Autodesk Fusion 360 part; units mm, degrees
(part 3 of 3)
sketch "草图3 (22)" plane through (286.45, 0, 0) normal (1, 0, 0) x (0, 0, -1) in component "16_CPU_VERTICAL_SIDE_FLUSH_TO_BEAM"
  line L0 (-16, 22) -> (-16, 38)
  line L1 (-16, 38) -> (-108, 237.84)
  line L2 (-108, 237.84) -> (-124, 237.84)
  line L3 (-124, 237.84) -> (-16, 22)
extrude "CPU side diagonal" add sketch "草图3 (22)" along normal blind 16 bodies 36 in component "16_CPU_VERTICAL_SIDE_FLUSH_TO_BEAM"
ref_plane "工作平面1" through (0, -6, 0) normal (0, 1, 0) x (0, 0, 1) in component "16_PCI_INSET_SIDE_16_45mm"
sketch "草图1 (33)" plane through (0, -6, 0) normal (0, 1, 0) x (1, 0, 0) in component "16_PCI_INSET_SIDE_16_45mm"
  line L0 (12.45, 0, 12) -> (28.45, 0, 12)
  line L1 (28.45, 0, 12) -> (12, -140, 12)
  line L2 (12, -140, 12) -> (-4, -140, 12)
  line L3 (-4, -140, 12) -> (12.45, 0, 12)
extrude "PCI taper 16.45 over 140 mm height" add sketch "草图1 (33)" along normal blind 247.84 separate body contours L0 L1 L2 L3 in plane through (0, 6, 0) normal (0, 1, 0) makes body 37 in component "16_PCI_INSET_SIDE_16_45mm"
ref_plane "工作平面2" through (0, 0, 16) normal (0, 0, 1) x (1, 0, 0) in component "16_PCI_INSET_SIDE_16_45mm"
sketch "草图2 (24)" plane through (0, 0, 16) normal (0, 0, 1) x (1, 0, 0) in component "16_PCI_INSET_SIDE_16_45mm"
  line L0 (-4.1, 22) -> (28.6, 22)
  line L1 (28.6, 22) -> (28.6, 237.84)
  line L2 (28.6, 237.84) -> (-4.1, 237.84)
  line L3 (-4.1, 237.84) -> (-4.1, 22)
extrude "PCI side open window" cut sketch "草图2 (24)" along normal blind 108 bodies 37 in component "16_PCI_INSET_SIDE_16_45mm"
ref_plane "工作平面3" through (-4, 0, 0) normal (1, 0, 0) x (0, 1, 0) in component "16_PCI_INSET_SIDE_16_45mm"
sketch "草图3 (23)" plane through (-4, 0, 0) normal (1, 0, 0) x (0, 0, -1) in component "16_PCI_INSET_SIDE_16_45mm"
  line L0 (-16, 22) -> (-16, 38)
  line L1 (-16, 38) -> (-108, 237.84)
  line L2 (-108, 237.84) -> (-124, 237.84)
  line L3 (-124, 237.84) -> (-16, 22)
extrude "PCI diagonal before taper trim" add sketch "草图3 (23)" along normal blind 32.45 bodies 37 in component "16_PCI_INSET_SIDE_16_45mm"
ref_plane "工作平面4" through (0, -5.9, 0) normal (0, 1, 0) x (0, 0, 1) in component "16_PCI_INSET_SIDE_16_45mm"
sketch "草图4 (21)" plane through (0, -5.9, 0) normal (0, 1, 0) x (1, 0, 0) in component "16_PCI_INSET_SIDE_16_45mm"
  line L0 (-10, 0, 11.8) -> (12.45, 0, 11.8)
  line L1 (12.45, 0, 11.8) -> (-4, -140, 11.8)
  line L2 (-4, -140, 11.8) -> (-10, -140, 11.8)
  line L3 (-10, -140, 11.8) -> (-10, 0, 11.8)
extrude "Trim diagonal outer tapered face" cut sketch "草图4 (21)" along normal blind 248.1 contours L0 L1 L2 L3 in plane through (0, 5.9, 0) normal (0, 1, 0) bodies 37 in component "16_PCI_INSET_SIDE_16_45mm"
ref_plane "工作平面5" through (0, -5.9, 0) normal (0, 1, 0) x (0, 0, 1) in component "16_PCI_INSET_SIDE_16_45mm"
sketch "草图5 (20)" plane through (0, -5.9, 0) normal (0, 1, 0) x (1, 0, 0) in component "16_PCI_INSET_SIDE_16_45mm"
  line L0 (28.45, 0, 11.8) -> (40, 0, 11.8)
  line L1 (40, 0, 11.8) -> (40, -140, 11.8)
  line L2 (40, -140, 11.8) -> (12, -140, 11.8)
  line L3 (12, -140, 11.8) -> (28.45, 0, 11.8)
extrude "Trim diagonal inner tapered face" cut sketch "草图5 (20)" along normal blind 248.1 contours L0 L1 L2 L3 in plane through (0, 5.9, 0) normal (0, 1, 0) bodies 37 in component "16_PCI_INSET_SIDE_16_45mm"
component "03_FRONT_MOTHERBOARD_BEAM" placed x (1, 0, 0) y (0, 1, 0) z (0, 0, 1) at (0, 0, -50)
component "03_MID_MOTHERBOARD_BEAM" placed x (1, 0, 0) y (0, 1, 0) z (0, 0, 1) at (0, 0, -50)
component "03_REAR_MOTHERBOARD_BEAM" placed x (1, 0, 0) y (0, 1, 0) z (0, 0, 1) at (0, 0, -50)
component "09_FRONT_DUAL_FAN_CARRIER" placed x (1, 0, 0) y (0, 1, 0) z (0, 0, 1) at (0, 0, -50)
component "10_GPU_140_FAN_MOUNT" placed x (1, 0, 0) y (0, 1, 0) z (0, 0, 1) at (0, 0, -50)
component "10_CPU_140_FAN_MOUNT" placed x (1, 0, 0) y (0, 1, 0) z (0, 0, 1) at (0, 0, -50)
component "REF_CASE_FAN_GPU_140x140x25" placed x (1, 0, 0) y (0, 1, 0) z (0, 0, 1) at (0, 0, -50)
component "REF_AIRFLOW_GPU_FRONT_TO_REAR" placed x (1, 0, 0) y (0, 1, 0) z (0, 0, 1) at (0, 0, -50)
component "REF_CASE_FAN_CPU_140x140x25" placed x (1, 0, 0) y (0, 1, 0) z (0, 0, 1) at (0, 0, -50)
component "REF_AIRFLOW_CPU_FRONT_TO_REAR" placed x (1, 0, 0) y (0, 1, 0) z (0, 0, 1) at (0, 0, -50)
component "REF_BOARD_304.8x243.84_NUMBERED_HOLES" placed x (1, 0, 0) y (0, 1, 0) z (0, 0, 1) at (0, 0, -50)
component "REF_CPU_RIGHT" placed x (1, 0, 0) y (0, 1, 0) z (0, 0, 1) at (0, 0, -50)
component "REF_MEMORY_RIGHT_FRONT" placed x (1, 0, 0) y (0, 1, 0) z (0, 0, 1) at (0, 0, -50)
component "REF_PRIMARY_PCIE_X126.4_APPROX" placed x (1, 0, 0) y (0, 1, 0) z (0, 0, 1) at (0, 0, -50)
component "REF_SECOND_LONG_PCIE_X60_APPROX" placed x (1, 0, 0) y (0, 1, 0) z (0, 0, 1) at (0, 0, -50)
component "REF_GPU_FANS_TO_MINUS_X" placed x (1, 0, 0) y (0, 1, 0) z (0, 0, 1) at (0, 0, -50)
component "REF_GPU_FAN_MARKERS_MINUS_X" placed x (1, 0, 0) y (0, 1, 0) z (0, 0, 1) at (0, 0, -50)
component "04_front_GROUND_BAR_290mm_FLAT_PSU" placed x (1, 0, 0) y (0, 1, 0) z (0, 0, 1) at (0, 0, 0)
component "04_rear_GROUND_BAR_290mm_FLAT_PSU" placed x (1, 0, 0) y (0, 1, 0) z (0, 0, 1) at (0, 0, 0)
component "05_CENTERED_FLAT_PSU_CRADLE_OPEN_INTAKE" placed x (1, 0, 0) y (0, 1, 0) z (0, 0, 1) at (0, 0, 0)
component "REF_PSU_FLAT_CENTERED_150x140x86" placed x (1, 0, 0) y (0, 1, 0) z (0, 0, 1) at (0, 0, 0)
component "REF_PSU_INTAKE_DOWN_MINUS_Z" placed x (1, 0, 0) y (0, 1, 0) z (0, 0, 1) at (0, 0, 0)
component "REF_PSU_REAR_EXHAUST_PLUS_Y" placed x (1, 0, 0) y (0, 1, 0) z (0, 0, 1) at (0, 0, 0)
component "12_front_PCI_SUPPORT_FRAME" placed x (1, 0, 0) y (0, 1, 0) z (0, 0, 1) at (0, 0, 0)
component "12_front_CPU_SUPPORT_FRAME" placed x (1, 0, 0) y (0, 1, 0) z (0, 0, 1) at (0, 0, 0)
component "12_rear_PCI_SUPPORT_FRAME" placed x (1, 0, 0) y (0, 1, 0) z (0, 0, 1) at (0, 0, 0)
component "12_rear_CPU_SUPPORT_FRAME" placed x (1, 0, 0) y (0, 1, 0) z (0, 0, 1) at (0, 0, 0)
component "07_GPU_REINFORCED_REAR_TOWER" placed x (1, 0, 0) y (0, 1, 0) z (0, 0, 1) at (0, 0, 0)
component "08_GPU_UPPER_EAR_LEDGE_ADJUSTABLE" placed x (1, 0, 0) y (0, 1, 0) z (0, 0, 1) at (0, 0, 0)
component "08_GPU_LOWER_TWO_TAB_RECEIVER_ADJUSTABLE" placed x (1, 0, 0) y (0, 1, 0) z (0, 0, 1) at (0, 0, 0)
component "17_REAR_TOP_BEAM_SEAM_JOINER" placed x (1, 0, 0) y (0, 1, 0) z (0, 0, 1) at (0, 0, 0)
component "16_CPU_VERTICAL_SIDE_FLUSH_TO_BEAM" placed x (1, 0, 0) y (0, 1, 0) z (0, 0, 1) at (0, 0, 0)
component "16_PCI_INSET_SIDE_16_45mm" placed x (1, 0, 0) y (0, 1, 0) z (0, 0, 1) at (0, 0, 0)
equation "desk_limit = 290 mm" comment "V03 layout review; fixed profiles require regeneration"
equation "footprint_width = 290 mm" comment "V03 layout review; fixed profiles require regeneration"
equation "board_width = 304.8 mm" comment "V03 layout review; fixed profiles require regeneration"
equation "board_depth = 243.84 mm" comment "V03 layout review; fixed profiles require regeneration"
equation "board_bottom_height = 208 mm" comment "V03 layout review; fixed profiles require regeneration"
equation "approx_slot_x = 126.4 mm" comment "V03 layout review; fixed profiles require regeneration"
